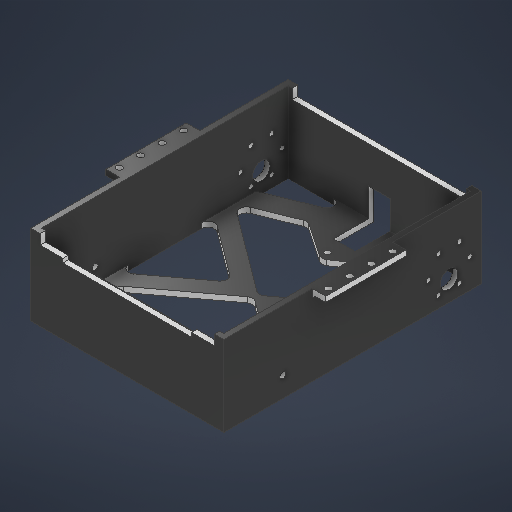
# Autodesk Inventor part: 01_4_2_support_electronique_moteur
Saved by Autodesk Inventor 2026 (Build 300175000, 175)
## iProperties
Created: 2025-06-04
Part Number: 01_4_2_support_electronique_moteur
Material: Générique
Document SubType Name: Modeling
Designer: virgi
Density: 1 g/cm^3
Appearance: Par défaut
Author: virgi
Autodesk Inventor part; units mm, degrees
ref_plane "YZ Plane" through (0, 0, 0) normal (1, 0, 0) x (0, 1, 0)
ref_plane "XZ Plane" through (0, 0, 0) normal (0, 1, 0) x (-1, 0, 0)
ref_plane "XY Plane" through (0, 0, 0) normal (0, 0, 1) x (1, 0, 0)
sketch "Esquisse1" plane through (0, 0, 0) normal (0, 1, 0) x (-1, 0, 0)
  line L0 (-72, -96) -> (72, -96)
  line L1 (72, -96) -> (72, 96)
  line L2 (72, 96) -> (-72, 96)
  line L3 (-72, 96) -> (-72, -96)
  line L4 (-72, -96) -> (72, 96) construction
  line L5 (72, -96) -> (-72, 96) construction
  point P0 (0, 0)
  dimension "d0" = 192
  dimension "d1" = 144
  constraints: 12 end point, 2 midpoint, 2 parallel, 1 horizontal, 1 perpendicular
  measures "d0" distance of L0.end L1.end
  measures "d1" distance of L0.start L0.end
extrude "bloc initial" add sketch "Esquisse1" along normal blind 60
sketch "Esquisse2" plane through (0, 60, 0) normal (0, 1, 0) x (1, 0, 0)
  line L0 (68, 92) -> (-68, 92)
  line L1 (-68, 92) -> (-68, -92)
  line L2 (-68, -92) -> (68, -92)
  line L3 (68, -92) -> (68, 92)
  line L4 (68, 92) -> (-68, -92) construction
  line L5 (-68, 92) -> (68, -92) construction
  line L6 (-72, -96) -> (72, -96) projected
  line L7 (-72, 96) -> (-72, -96) projected
  point P0 (0, 0)
  dimension "d4" = 4
  dimension "d5" = 4
  constraints: 12 end point, 2 midpoint, 2 parallel, 1 horizontal, 1 perpendicular
  measures "d4" distance between parallel lines of L6 L2
  measures "d5" distance between parallel lines of L7 L1
extrude "volume interieur" cut sketch "Esquisse2" against normal blind 56
sketch "Esquisse3" plane through (0, 60, 0) normal (0, 1, 0) x (1, 0, 0)
  line L0 (-68, 30) -> (-82, 30)
  line L1 (-82, 30) -> (-82, -30)
  line L2 (-82, -30) -> (-68, -30)
  line L3 (-68, -30) -> (-68, 30)
  line L4 (-68, 30) -> (-82, -30) construction
  line L5 (-82, 30) -> (-68, -30) construction
  line L6 (-68, -92) -> (-68, 92) projected
  line L7 (-72, 96) -> (-72, -96) projected
  point P0 (0, 0)
  point P1 (-75, 0)
  point P2 (-72, -30)
  point P3 (-72, 30)
  dimension "d12" = 10
  dimension "d13" = 60
  dimension "d14" = 0
  constraints: 12 end point, 2 midpoint, 2 parallel, 1 collinear, 1 horizontal, 1 perpendicular
  measures "d12" distance between parallel lines of L7 L1
  measures "d13" distance between parallel lines of L0 L2
  measures "d14" vertical distance of point (0, 0) point (-75, 0)
extrude "vorsprung de maintient" add sketch "Esquisse3" against normal blind 4 contours L7 L2 L1 L0
sketch "Esquisse4" plane through (0, 60, 0) normal (0, 1, 0) x (1, 0, 0)
  line L0 (-82, 30) -> (-82, -30) projected
  line L1 (-72, 30) -> (-82, 30) projected
  point P0 (0, 0)
  point P1 (-78, 24)
  dimension "d24" = 4
  dimension "d25" = 6
  measures "d24" distance from line of L0 point (-78, 24)
  measures "d25" distance from line of L1 point (-78, 24)
hole "8*trous attache chassis" at (-78, 60, -24) direction (0, -1, 0) diameter 4.5 end through all
pattern_linear "Réseau rectangulaire1" count 4 spacing 16 along (0, 0, 1) of "8*trous attache chassis"
mirror "Mise en miroir2" about plane through (0, 0, 0) normal (1, 0, 0) of "vorsprung de maintient", "8*trous attache chassis", "Réseau rectangulaire1"
sketch "Esquisse5" plane through (0, 60, 0) normal (0, 1, 0) x (1, 0, 0)
  line L0 (-65, 71) -> (65, 71)
  line L1 (65, 71) -> (65, 101)
  line L2 (65, 101) -> (-65, 101)
  line L3 (-65, 101) -> (-65, 71)
  line L4 (-65, 71) -> (65, 101) construction
  line L5 (65, 71) -> (-65, 101) construction
  point P0 (0, 0)
  point P1 (0, 86)
  dimension "d29" = 71
  dimension "d30" = 30
  dimension "d31" = 130
  dimension "d32" = 0
  constraints: 12 end point, 2 midpoint, 2 parallel, 1 horizontal, 1 perpendicular
  measures "d29" distance from line of point (0, 0) L0
  measures "d30" distance between parallel lines of L2 L0
  measures "d31" distance between parallel lines of L3 L1
  measures "d32" horizontal distance of point (0, 0) point (0, 86)
extrude "encoches chassis" cut sketch "Esquisse5" against normal blind 7.5
mirror "Mise en miroir encoches" about plane through (0, 0, 0) normal (0, 0, 1) of "encoches chassis"
sketch "Esquisse7" plane through (-72, 0, -96) normal (-1, 0, 0) x (0, 0, 1)
  line L0 (192, 0) -> (192, 60) projected
  line L1 (0, 0) -> (192, 0) projected
  line L2 (126, 60) -> (192, 60) projected
  point P0 (96, 0)
  point P1 (148, 15)
  point P2 (192, 52.5)
  point P3 (167, 60)
  dimension "d47" = 44
  dimension "d49" = 45
  measures "d47" distance from line of L0 point (148, 15)
  measures "d49" distance from line of L2 point (148, 15)
hole "axe roues arrieres" at (-72, 15, 52) direction (1, 0, 0) diameter 4.5 end through all
sketch "Esquisse8" plane through (-72, 0, -96) normal (-1, 0, 0) x (0, 0, 1)
  line L0 (0, 60) -> (66, 60) projected
  line L1 (0, 0) -> (0, 60) projected
  line L2 (0, 0) -> (192, 0) projected
  point P0 (96, 0)
  point P1 (24, 15)
  point P2 (25, 60)
  point P3 (0, 52.5)
  point P4 (96, 0)
  dimension "d57" = 45
  dimension "d60" = 72
  constraints: 1 midpoint
  measures "d57" distance from line of point (24, 15) L0
  measures "d60" horizontal distance of point (24, 15) point (96, 0)
hole "axes moteur" at (-72, 15, -72) direction (1, 0, 0) diameter 13.2 end through all
sketch "Esquisse9" plane through (-72, 0, -96) normal (-1, 0, 0) x (0, 0, 1)
  circle A0 centre (24, 22) radius 15.5 construction
  circle A1 centre (24, 15) radius 6.6 construction
  point P0 (96, 0)
  point P1 (39.5, 22)
  point P2 (31.75, 35.4234)
  point P3 (16.25, 35.4234)
  point P4 (8.5, 22)
  point P5 (16.25, 8.5766)
  point P6 (31.75, 8.5766)
  dimension "d70" = 31
  dimension "d68" = 7
  dimension "d69" = 0
  dimension "d71" = 0
  dimension "d74" = 360
  constraints: 2 coincident, 1 horizontal alignment, 13 other
  measures "d68" distance of A1.centre point (24, 22)
  measures "d69" horizontal distance of A1.centre point (24, 22)
  measures "d71" vertical distance of point (24, 22) point (39.5, 22)
hole "trous moteur" at (-72, 22, -56.5) at (-72, 35.4234, -64.25) at (-72, 35.4234, -79.75) at (-72, 22, -87.5) at (-72, 8.5766, -79.75) at (-72, 8.5766, -64.25) direction (1, 0, 0) diameter 3.5 end through all
sketch "Esquisse12" plane through (0, 60, 0) normal (0, 1, 0) x (1, 0, 0)
  line L0 (-48, -96) -> (48, -96)
  line L1 (48, -96) -> (48, -92)
  line L2 (48, -92) -> (-48, -92)
  line L3 (-48, -92) -> (-48, -96)
  line L4 (-48, -96) -> (48, -92) construction
  line L5 (48, -96) -> (-48, -92) construction
  line L6 (65, -96) -> (-65, -96) projected
  line L7 (-65, -92) -> (65, -92) projected
  point P0 (0, 0)
  point P1 (0, -94)
  point P2 (62, -96)
  point P3 (-62, -96)
  point P4 (-58, -92)
  point P5 (58, -92)
  dimension "d106" = 96
  dimension "d109" = 0
  constraints: 12 end point, 2 collinear, 2 midpoint, 2 parallel, 1 horizontal, 1 perpendicular
  measures "d106" distance between parallel lines of L3 L1
  measures "d109" horizontal distance of point (0, 0) point (0, -94)
extrude "encoche chassis arriere" cut sketch "Esquisse12" against normal blind 10.5
chamfer "Chanfrein2" distance 2 angle 45 2 edges at (-72, 56, 0) (72, 56, 0)
sketch "Esquisse13" plane through (0, 4, 0) normal (0, 1, 0) x (1, 0, 0)
  line L0 (0, 1.362) -> (-68, 52)
  line L1 (68, 52) -> (0, 1.362)
  line L2 (0, -116.7872) -> (0, 160.5594) construction
  line L3 (-68, -92) -> (-68, 92) projected
  line L4 (-77.1225, 0) -> (59.0886, 0) construction
  line L5 (-74.2887, 0) -> (57.0105, 0) construction
  line L6 (0, -1.362) -> (-68, -52)
  line L7 (-68, -52) -> (68, -52)
  line L8 (68, -52) -> (0, -1.362)
  line L9 (-18.2627, 0) -> (-68, -37.0382)
  line L10 (-68, -37.0382) -> (-68, 37.0382)
  line L11 (-18.2627, 0) -> (-68, 37.0382)
  line L12 (-68, -37.0382) -> (-68, 37.0382)
  line L13 (18.2627, 0) -> (68, -37.0382)
  line L14 (68, -37.0382) -> (68, 37.0382)
  line L15 (18.2627, 0) -> (68, 37.0382)
  line L16 (-68, 52) -> (-29, 67.8231)
  line L17 (8.4839, 92) -> (68, 67.853)
  line L18 (68, 67.853) -> (68, 92)
  line L19 (68, 92) -> (8.4839, 92)
  line L20 (68, 92) -> (68, -92) projected
  line L21 (65, 92) -> (-65, 92) projected
  line L22 (-8.4839, 92) -> (-68, 67.853)
  line L23 (-68, 67.853) -> (-68, 92)
  line L24 (-68, 92) -> (-8.4839, 92)
  line L25 (-48, -92) -> (48, -92) projected
  line L26 (-65, 96) -> (65, 96) projected
  line L27 (8.125, 96) -> (8.125, 65.9) construction
  line L28 (8.125, 96) -> (38.225, 96) construction
  line L29 (8.125, 65.9) -> (0, 65.9) construction
  line L30 (8.125, 96) -> (0, 96) construction
  line L31 (-8.125, 96) -> (-8.125, 65.9) construction
  line L32 (-8.125, 65.9) -> (0, 65.9) construction
  line L33 (-8.125, 96) -> (0, 96) construction
  circle A0 centre (-1.5, 54.9) radius 2 construction
  line L34 (-29, 67.8231) -> (0, 48.2272)
  line L35 (29, 67.8231) -> (0, 48.2272)
  line L36 (29, 67.8231) -> (68, 52)
  point P0 (0, 0)
  point P1 (-58, -71)
  point P2 (-58, 71)
  point P3 (0, 83.6463)
  point P4 (58, 71)
  point P5 (58, -71)
  point P6 (58, 92)
  point P7 (-58, 92)
  point P8 (-58, 92)
  point P9 (-68, 67.853)
  point P10 (-62, 96)
  point P11 (62, 96)
  point P12 (68, -92)
  dimension "d114" = 12
  dimension "d126" = 40
  dimension "d136" = 30.1
  dimension "d137" = 90
  dimension "d138" = 8.125
  dimension "d139" = 4
  dimension "d142" = 11
  dimension "d143" = 9.625
  dimension "d144" = 35
  constraints: 64 end point, 13 symmetric about line, 11 point on line, 4 vertical, 3 parallel, 3 perpendicular, 2 horizontal, 1 centre point, 1 midpoint, 6 other
  measures "d114" distance from line of L11 L0.start
  measures "d126" distance between parallel lines of L25 L7
  measures "d136" distance of L27.start L27.end
  measures "d137" angle of L27 L28
  measures "d138" distance of L27.end L29.end
  measures "d139" diameter of A0
  measures "d142" distance from line of L29 A0.centre
  measures "d143" distance from line of L27 A0.centre
  measures "d144" distance of L16.end L34.end
extrude "structure bas" cut sketch "Esquisse13" against normal blind 10 contours L0 L16 L34 L35 L36 L1 | L11 L9 L3 | L3 L24 L21 L22 | L17 L19 L18 | L14 L13 L15 | L6 L8 L7
sketch "Esquisse14" plane through (0, 4, 0) normal (0, 1, 0) x (1, 0, 0)
  line L0 (-68, -56) -> (68, -56)
  line L1 (68, -56) -> (68, -58)
  line L2 (68, -58) -> (-68, -58)
  line L3 (-68, -58) -> (-68, -56)
  line L4 (-48, -92) -> (48, -92) projected
  point P0 (0, 0)
  point P1 (68, -92)
  point P2 (-68, -92)
  dimension "d117" = 34
  dimension "d118" = 2
  constraints: 8 end point, 2 parallel, 2 point on line, 1 horizontal, 1 perpendicular
  measures "d117" distance between parallel lines of L4 L2
  measures "d118" distance between parallel lines of L2 L0
extrude "Extrusion8" add sketch "Esquisse14" along normal blind 10
chamfer "Chanfrein3" distance 2 angle 45 1 edges at (0, 4, 56)
fillet "Congé1" radius 5 18 edges at (68, 2, -52) (0, 2, -1.362) (0, 2, 1.362) (68, 2, 52) (68, 2, 37.0382) (68, 2, -37.0382) (-18.2627, 2, 0) (-68, 2, -37.0382) (-68, 2, -52) (-8.4839, 2, -92) (8.4839, 2, -92) (68, 2, -67.853) (-68, 2, 37.0382) (-68, 2, 52) (18.2627, 2, 0) (29, 2, -67.8231) (-29, 2, -67.8231) (0, 2, -48.2272)
sketch "Esquisse15" plane through (0, 0, 0) normal (0, -1, 0) x (1, 0, 0)
  line L0 (72, -96) -> (-72, -96) projected
  line L1 (8.125, -96) -> (8.125, -65.9)
  line L2 (8.125, -96) -> (38.225, -96) construction
  line L3 (8.125, -65.9) -> (0, -65.9)
  line L4 (0, -162.9029) -> (0, 159.6719) construction
  line L5 (8.125, -96) -> (0, -96)
  line L6 (-8.125, -96) -> (-8.125, -65.9)
  line L7 (-8.125, -65.9) -> (0, -65.9)
  line L8 (-8.125, -96) -> (0, -96)
  circle A0 centre (-1.5, -54.9) radius 2
  point P0 (0, 0)
  dimension "d129" = 30.1
  dimension "d130" = 90
  dimension "d131" = 8.125
  dimension "d132" = 4
  dimension "d133" = 11
  dimension "d145" = 9.625
  constraints: 16 end point, 3 point on line, 3 vertical, 2 perpendicular, 2 symmetric about line, 1 centre point, 1 horizontal, 1 midpoint
  measures "d129" distance of L1.start L1.end
  measures "d130" angle of L2 L1
  measures "d131" distance of L1.end L3.end
  measures "d132" diameter of A0
  measures "d133" distance from line of L7 A0.centre
  measures "d145" distance from line of L1 A0.centre
extrude "Extrusion9" cut sketch "Esquisse15" against normal blind 25.15
